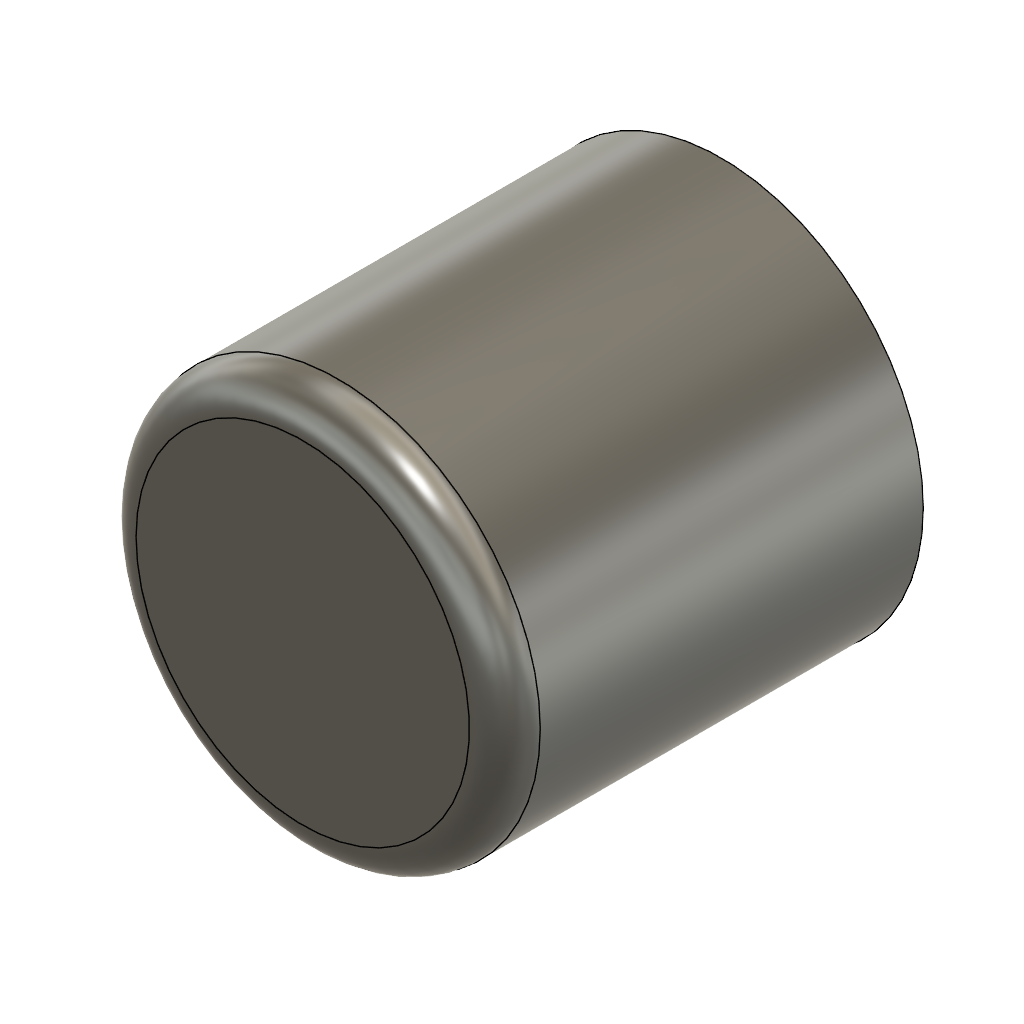
Native (Autodesk Fusion 360 design; units mm, degrees)
part number: 2026-11-25-23-03-09-437
Autodesk Fusion 360 part; units mm, degrees
sketch "Disc sketch" plane through (0, 0, 0) normal (0, 0, 1) x (1, 0, 0)
  circle A0 centre (0, 0) radius 21.1
extrude "Disc extrude" add sketch "Disc sketch" along normal blind 43.7
fillet "Rim round" radius 3.7 1 edges at (-19.6721, -7.6301, 43.7)
